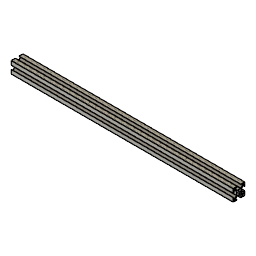
len_alluminium_v5 (Autodesk Fusion 360 design; units mm, degrees)
part number: 2026-11-03-22-05-18-122
Autodesk Fusion 360 part; units mm, degrees
sketch "Sketch1" plane through (0, 0, 0) normal (1, 0, 0) x (0, 1, 0)
  line L0 (10, 10) -> (-10, 10)
  line L1 (-10, 10) -> (-10, -10)
  line L2 (-10, -10) -> (10, -10)
  line L3 (10, -10) -> (10, 10)
  line L4 (10, 10) -> (-10, -10) construction
  line L5 (-10, 10) -> (10, -10) construction
  line L6 (4, 4) -> (-4, 4)
  line L7 (-4, 4) -> (-4, -4)
  line L8 (-4, -4) -> (4, -4)
  line L9 (4, -4) -> (4, 4)
  line L10 (4, 4) -> (-4, -4) construction
  line L11 (-4, 4) -> (4, -4) construction
  line L12 (10, -10) -> (3, -10)
  line L13 (3, -10) -> (3, -3)
  line L14 (3, -3) -> (10, -3)
  line L15 (10, -3) -> (10, -10)
  circle A0 centre (0, 0) radius 1.75
  line L16 (8.5, -8.5) -> (4.5, -8.5)
  line L17 (4.5, -8.5) -> (4.5, -4.5)
  line L18 (4.5, -4.5) -> (8.5, -4.5)
  line L19 (8.5, -4.5) -> (8.5, -8.5)
  line L20 (0, 0) -> (10, -10)
  line L21 (-10.5303, 9.4697) -> (9.4697, -10.5303)
  line L22 (-9.4697, 10.5303) -> (10.5303, -9.4697)
  line L23 (0, 2.5) -> (0, 20)
  line L24 (9.4697, 10.5303) -> (-10.5303, -9.4697)
  line L25 (10.5303, 9.4697) -> (-9.4697, -10.5303)
  line L26 (10, 3) -> (3, 3)
  line L27 (8.5, 4.5) -> (4.5, 4.5)
  line L28 (3, 3) -> (3, 10)
  line L29 (4.5, 4.5) -> (4.5, 8.5)
  line L30 (4.5, 8.5) -> (8.5, 8.5)
  line L31 (8.5, 8.5) -> (8.5, 4.5)
  line L32 (-3, 10) -> (-3, 3)
  line L33 (-4.5, 8.5) -> (-4.5, 4.5)
  line L34 (-3, 3) -> (-10, 3)
  line L35 (-4.5, 4.5) -> (-8.5, 4.5)
  line L36 (-8.5, 4.5) -> (-8.5, 8.5)
  line L37 (-8.5, 8.5) -> (-4.5, 8.5)
  line L38 (-10, -3) -> (-3, -3)
  line L39 (-8.5, -4.5) -> (-4.5, -4.5)
  line L40 (-3, -3) -> (-3, -10)
  line L41 (-4.5, -4.5) -> (-4.5, -8.5)
  line L42 (-4.5, -8.5) -> (-8.5, -8.5)
  line L43 (-8.5, -8.5) -> (-8.5, -4.5)
  line L44 (-10, -3) -> (-3, -10)
  line L45 (10, -3) -> (3, -10)
  line L46 (1.75, 0) -> (22.5, 0)
  line L47 (-10, 3) -> (-3, 10)
  line L48 (10, 3) -> (3, 10)
  dimension "d1" = 20
  dimension "d2" = 20
  dimension "d11" = 10
  dimension "d12" = 10
  dimension "d13" = 8
  dimension "d14" = 8
  dimension "d15" = 7
  dimension "d16" = 7
  dimension "d17" = 3.5
  dimension "d18" = 1.5
  dimension "d19" = 0.75
  dimension "d20" = -1.5
  dimension "d22" = 360
  constraint horizontal L6
  constraint perpendicular L6 L7
  constraint parallel L6 L8
  constraint parallel L7 L9
  constraint coincident L10 A0.centre
  constraint coincident L11 A0.centre
  constraint coincident A0.centre L20.start
  constraint horizontal L12
  constraint vertical L13
  constraint horizontal L14
  constraint vertical L15
  constraint parallel L5 L20
  constraint symmetric L21.start L23 L25.start
  constraint symmetric L21.end L23 L25.end
  constraint symmetric L22.start L23 L24.start
  constraint symmetric L22.end L23 L24.end
  constraint symmetric L23 L38.start L14.end
  constraint symmetric L23 L40.end L12.end
  constraint symmetric L38.start L46 L34.end
  constraint symmetric L40.end L46 L32.start
  constraint symmetric L14.end L46 L26.start
  constraint symmetric L12.end L46 L28.end
  measures "d1" distance of L1.end L2.end
  measures "d2" distance of L0.end L1.end
  measures "d11" distance of A0.centre L0
  measures "d12" distance of A0.centre L3
  measures "d13" distance of L7.end L8.end
  measures "d14" distance of L6.end L7.end
  measures "d15" distance of L2.end L12.end
  measures "d16" distance of L2.end L14.end
  measures "d17" diameter of A0
extrude "Extrude2" add sketch "Sketch1" along normal mid plane 380 contours L0 L3 L24 L25 L30 L31 | L0 L24 L30 L48 | L3 L25 L31 L48 | L24 L25 L30 L31 L48 | L6 L9 L24 L25 L26 L27 L28 L29 | L24 L25 L27 L29 L48 | L0 L22 L37 L47 | L6 A0 L22 L24 | L6 L9 A0 L24 L25 L26 L28 | L6 L9 L26 L28 | L3 L15 L19 L22 L45 | L9 A0 L25 L46 | L9 A0 L22 L46 | L0 L1 L21 L22 L36 L37 | L6 L7 L21 L22 L32 L33 L34 L35 | L6 L7 A0 L21 L22 L32 L34 | L3 L15 L19 L20 L22 | L9 L14 L18 L20 L22 | L9 L14 A0 L20 L22 | L21 L22 L36 L37 L47 | L21 L22 L33 L35 L47 | L6 L7 L32 L34 | L2 L12 L16 L20 L21 | L19 L20 L22 L45 | L9 L14 L20 | L18 L20 L22 L45 | L1 L21 L36 L47 | L7 A0 L21 L24 | L2 L12 L16 L21 L45 | L16 L20 L21 L45 | L8 L13 L17 L20 L21 | L8 L13 L20 | L8 L13 A0 L20 L21 | L17 L20 L21 L45 | L7 L8 A0 L24 L25 L38 L40 | L8 A0 L21 L25 | L1 L24 L43 L44 | L2 L25 L42 L44 | L1 L2 L24 L25 L42 L43 | L7 L8 L24 L25 L38 L39 L40 L41 | L7 L8 L38 L40 | L24 L25 L42 L43 L44 | L24 L25 L39 L41 L44
equation "d19 = ( 1.5 / 2 ) * 1 mm"
equation "d23 = ( 380 / 2 ) * 1 mm"
